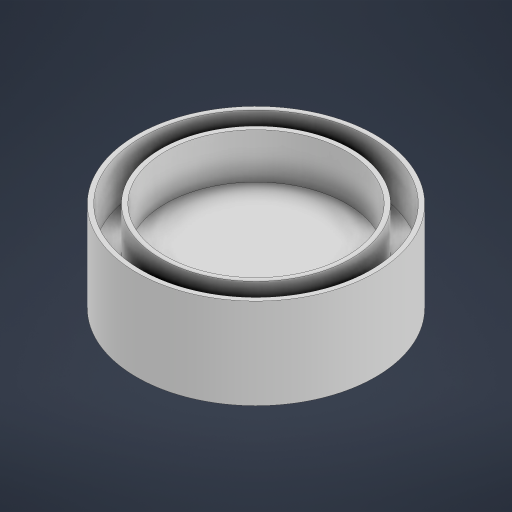
# Autodesk Inventor part: Base _mecflu
Saved by Autodesk Inventor 2024 (Build 280153000, 153)
## iProperties
Created: 2024-11-09
Part Number: Base _mecflu
Material: Genérico
Document SubType Name: Modeling
Designer: danil
Density: 1 g/cm^3
Appearance: Padrão
Author: danil
Autodesk Inventor part; units mm, degrees
ref_plane "YZ Plane" through (0, 0, 0) normal (1, 0, 0) x (0, 1, 0)
ref_plane "XZ Plane" through (0, 0, 0) normal (0, 1, 0) x (-1, 0, 0)
ref_plane "XY Plane" through (0, 0, 0) normal (0, 0, 1) x (1, 0, 0)
sketch "Esboço1" plane through (0, 0, 0) normal (0, 1, 0) x (-1, 0, 0)
  circle A0 centre (0, 0) radius 77
  dimension "d0" = 154
  constraints: 1 centre point, 1 coincident
  measures "d0" diameter of A0
extrude "Extrusão1" add sketch "Esboço1" along normal blind 30
sketch "Esboço2" plane through (0, 30, 0) normal (0, 1, 0) x (1, 0, 0)
  circle A0 centre (0, 0) radius 77
  circle A1 centre (0, 0) radius 75.5
  dimension "d3" = 151
  constraints: 2 centre point, 2 coincident
  measures "d3" diameter of A1
extrude "Extrusão2" add sketch "Esboço2" along normal blind 30
sketch "Esboço3" plane through (0, 30, 0) normal (0, 1, 0) x (1, 0, 0)
  circle A0 centre (0, 0) radius 61
  circle A1 centre (0, 0) radius 60
  dimension "d6" = 122
  dimension "d7" = 120
  constraints: 2 centre point, 2 coincident
  measures "d6" diameter of A0
  measures "d7" diameter of A1
extrude "Extrusão3" add sketch "Esboço3" along normal blind 30
sketch "Esboço4" plane through (0, 60, 0) normal (0, 1, 0) x (1, 0, 0)
  circle A0 centre (0, 0) radius 61.5
  circle A1 centre (0, 0) radius 60
  circle A2 centre (0, 0) radius 78
  circle A3 centre (0, 0) radius 76.5
  dimension "d10" = 123
  dimension "d11" = 156
  dimension "d12" = 153
  constraints: 4 centre point, 4 coincident
  measures "d10" diameter of A0
  measures "d11" diameter of A2
  measures "d12" diameter of A3
extrude "Extrusão4" add sketch "Esboço4" against normal blind 40 contours A0
sketch "Esboço5" plane through (0, 60, 0) normal (0, 1, 0) x (1, 0, 0)
  circle A0 centre (0, 0) radius 78
  circle A1 centre (0, 0) radius 76.5
  dimension "d15" = 156
  dimension "d16" = 153
  constraints: 2 centre point, 2 coincident
  measures "d15" diameter of A0
  measures "d16" diameter of A1
extrude "Extrusão5" add sketch "Esboço5" against normal blind 60
sketch "Esboço6" plane through (0, 60, 0) normal (0, 1, 0) x (1, 0, 0)
  circle A0 centre (0, 0) radius 75.5
  circle A1 centre (0, 0) radius 76.5
  dimension "d19" = 151
  dimension "d20" = 153
  constraints: 2 centre point, 2 coincident
  measures "d19" diameter of A0
  measures "d20" diameter of A1
extrude "Extrusão6" cut sketch "Esboço6" against normal blind 30
sketch "Esboço7" plane through (0, 60, 0) normal (0, 1, 0) x (1, 0, 0)
  circle A0 centre (0, 0) radius 63
  circle A1 centre (0, 0) radius 60
  dimension "d23" = 126
  dimension "d24" = 120
  constraints: 2 centre point, 2 coincident
  measures "d23" diameter of A0
  measures "d24" diameter of A1
extrude "Extrusão7" add sketch "Esboço7" against normal blind 30
sketch "Esboço8" plane through (0, 60, 0) normal (0, 1, 0) x (1, 0, 0)
  circle A0 centre (0, 0) radius 76
  circle A1 centre (0, 0) radius 79
  dimension "d27" = 152
  dimension "d28" = 158
  constraints: 2 centre point, 2 coincident
  measures "d27" diameter of A0
  measures "d28" diameter of A1
extrude "Extrusão8" add sketch "Esboço8" against normal blind 60
